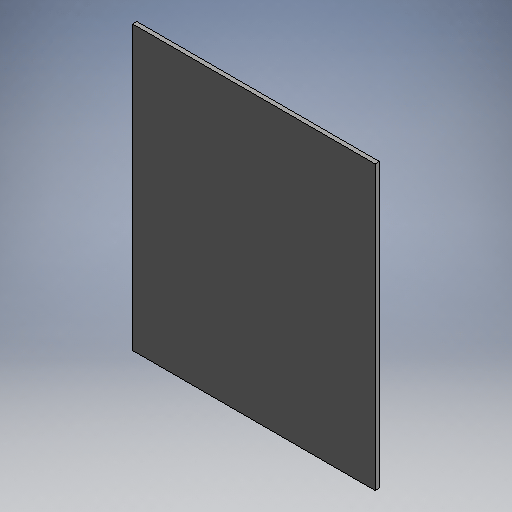
# Autodesk Inventor part: Fence_Panel_6ft_H-5610-7
Saved by Autodesk Inventor 2026.2 (Build 302298000, 298)
## iProperties
Part Number: Fence_Panel_6ft_H-5610-7
Material: Generic
Document SubType Name: Modeling
Designer: Jacob
Appearance: Default
Author: Jacob
Autodesk Inventor part; units mm, degrees
ref_plane "YZ Plane" through (0, 0, 0) normal (1, 0, 0) x (0, 1, 0)
ref_plane "XZ Plane" through (0, 0, 0) normal (0, 1, 0) x (-1, 0, 0)
ref_plane "XY Plane" through (0, 0, 0) normal (0, 0, 1) x (1, 0, 0)
sketch "Sketch1" plane through (0, 0, 0) normal (0, 0, 1) x (1, 0, 0)
  line L0 (-914.4, 0) -> (914.4, 0)
  line L1 (914.4, 0) -> (914.4, 2133.6)
  line L2 (914.4, 2133.6) -> (-914.4, 2133.6)
  line L3 (-914.4, 2133.6) -> (-914.4, 0)
  line L4 (-882.4, 32) -> (882.4, 32)
  line L5 (882.4, 32) -> (882.4, 2101.6)
  line L6 (882.4, 2101.6) -> (-882.4, 2101.6)
  line L7 (-882.4, 2101.6) -> (-882.4, 32)
  constraints: 16 end point, 4 parallel, 2 horizontal, 2 perpendicular
extrude "Extrusion1" add sketch "Sketch1" along normal blind 32 contours L3 L2 L1 L0 | L7 L6 L5 L4
sketch "Sketch2" plane through (0, 0, 0) normal (0, 0, 1) x (1, 0, 0)
  line L0 (-884.4, 30) -> (884.4, 30)
  line L1 (884.4, 30) -> (884.4, 2103.6)
  line L2 (884.4, 2103.6) -> (-884.4, 2103.6)
  line L3 (-884.4, 2103.6) -> (-884.4, 30)
  constraints: 8 end point, 2 parallel, 1 horizontal, 1 perpendicular
extrude "Extrusion2" add sketch "Sketch2" along normal blind 4
body "Solid1"
